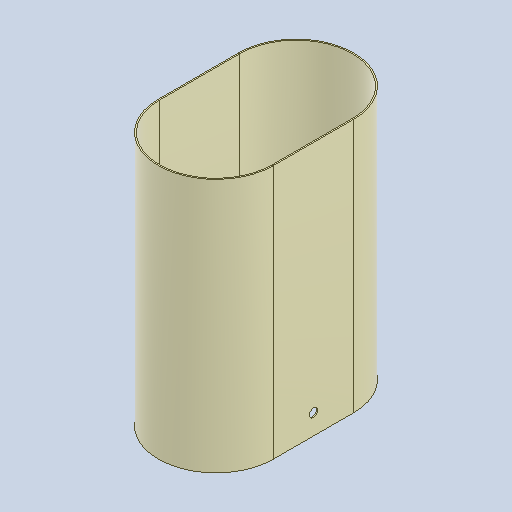
# Autodesk Inventor part: RDS-1102 Tank Shell PP
Saved by Autodesk Inventor 2026.2 (Build 302298000, 298)
## iProperties
Created: 2026-10-18
Part Number: RDS-1102 Tank Shell PP
Material: Polypropylene
Description: Tank shell, polypropylene
Document SubType Name: Modeling
Designer: admin
Stock Number: Обечайка ёмкости ПП
Density: 0.899 g/cm^3
Appearance: Smooth - Ash
Mass: 66081.5 g
Surface Area: 147805 cm^2
Volume: 73505.5 cm^3
Author: admin
Autodesk Inventor part; units mm, degrees
ref_plane "YZ Plane" through (0, 0, 0) normal (1, 0, 0) x (0, 1, 0)
ref_plane "XZ Plane" through (0, 0, 0) normal (0, 1, 0) x (-1, 0, 0)
ref_plane "XY Plane" through (0, 0, 0) normal (0, 0, 1) x (1, 0, 0)
sketch "Sketch1" plane through (0, 0, 0) normal (0, 1, 0) x (-1, 0, 0)
  line L0 (-430, -300) -> (-430, 300)
  line L1 (430, 300) -> (430, -300)
  arc A0 (430, 300) -> (-430, 300) centre (0, 300) ccw
  arc A1 (-430, -300) -> (430, -300) centre (0, -300) ccw
  line L2 (-420, -300) -> (-420, 300)
  line L3 (420, 300) -> (420, -300)
  arc A2 (420, 300) -> (-420, 300) centre (0, 300) ccw
  arc A3 (-420, -300) -> (420, -300) centre (0, -300) ccw
  dimension "d0" = 430
  dimension "d1" = 600
  dimension "d2" = 420
  dimension "d3" = 600
  constraints: 8 end point, 8 point on circle, 8 tangent, 4 centre point, 2 equal radius, 1 coincident
  measures "d0" radius of A0
  measures "d1" distance of L0.start L0.end
  measures "d2" radius of A2
  measures "d3" distance of L2.start L2.end
extrude "Shell" add sketch "Sketch1" along normal blind 1900
sketch "Outlet Hole Sketch" plane through (430, 0, 300) normal (1, 0, 0) x (0, 0, -1)
  circle A0 centre (300, 150) radius 31.5
  dimension "d6" = 63
  constraints: 1 centre point
  measures "d6" diameter of A0
extrude "Outlet Hole" cut sketch "Outlet Hole Sketch" against normal blind 20
equation "\"d0\" = 0.5 * Shell1102_Width"
equation "\"d1\" = Shell1102_Length - Shell1102_Width"
equation "\"d2\" = -Shell1102_Wall_Thickness + 0.5 * Shell1102_Width"
equation "\"d3\" = 0 * Shell1102_Wall_Thickness + Shell1102_Length - Shell1102_Width"
equation "\"d4\" = Shell1102_Height"
equation "\"d6\" = Shell1102_Outlet_Hole_Diam"
equation "\"d7\" = 2 * Shell1102_Wall_Thickness"
equation "\"Shell1102_Length\" = 1460"
equation "\"Shell1102_Width\" = 860"
equation "\"Shell1102_Height\" = 1900"
equation "\"Shell1102_Outlet_Hole_Diam\" = 63"
equation "\"Shell1102_Wall_Thickness\" = 10"
body "Solid1"
